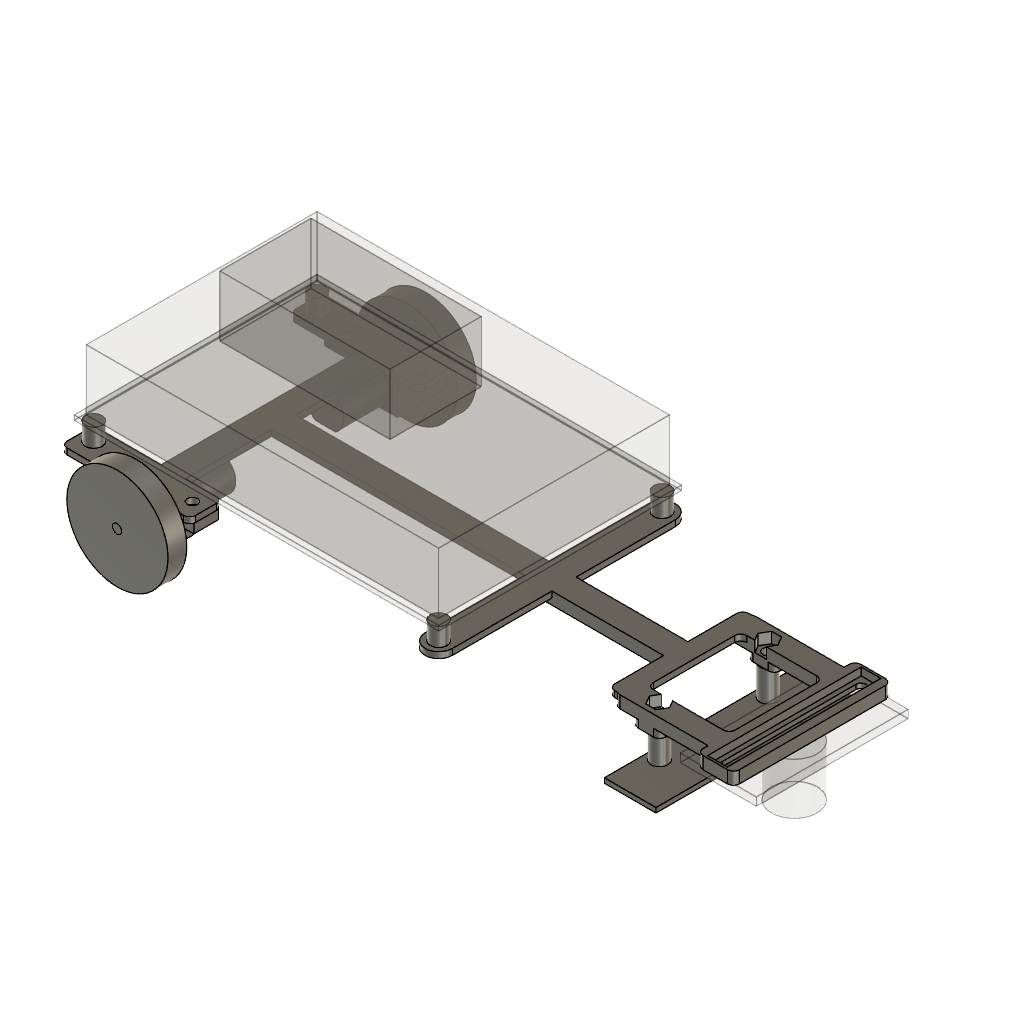
line_follower_chassis_front_caster (Autodesk Fusion 360 design; units mm, degrees)
Autodesk Fusion 360 part; units mm, degrees
ref_plane "WorkPlane1" through (0, 0, 21.65) normal (0, 0, 1) x (1, 0, 0) in component "Frame"
sketch "outline" plane through (0, 0, 21.65) normal (0, 0, 1) x (1, 0, 0) in component "Frame"
  line L0 (-24.25, -43) -> (14.0909, -43)
  line L1 (16.0909, -41) -> (16.0909, -34.25)
  line L2 (14.0909, -32.25) -> (-24.25, -32.25)
  line L3 (-26.25, -34.25) -> (-26.25, -41)
  arc A0 (14.0909, -43) -> (16.0909, -41) centre (14.0909, -41) ccw
  arc A1 (16.0909, -34.25) -> (14.0909, -32.25) centre (14.0909, -34.25) ccw
  arc A2 (-24.25, -32.25) -> (-26.25, -34.25) centre (-24.25, -34.25) ccw
  arc A3 (-26.25, -41) -> (-24.25, -43) centre (-24.25, -41) ccw
  line L4 (137, -22.35) -> (170, -22.35)
  line L5 (172, -20.35) -> (172, -17.4)
  line L6 (170, -15.4) -> (137, -15.4)
  line L7 (135, -17.4) -> (135, -20.35)
  arc A4 (170, -22.35) -> (172, -20.35) centre (170, -20.35) ccw
  arc A5 (172, -17.4) -> (170, -15.4) centre (170, -17.4) ccw
  arc A6 (137, -15.4) -> (135, -17.4) centre (137, -17.4) ccw
  arc A7 (135, -20.35) -> (137, -22.35) centre (137, -20.35) ccw
  line L8 (-24.25, 32.25) -> (14.0909, 32.25)
  line L9 (16.0909, 34.25) -> (16.0909, 41)
  line L10 (14.0909, 43) -> (-24.25, 43)
  line L11 (-26.25, 41) -> (-26.25, 34.25)
  arc A8 (14.0909, 32.25) -> (16.0909, 34.25) centre (14.0909, 34.25) ccw
  arc A9 (16.0909, 41) -> (14.0909, 43) centre (14.0909, 41) ccw
  arc A10 (-24.25, 43) -> (-26.25, 41) centre (-24.25, 41) ccw
  arc A11 (-26.25, 34.25) -> (-24.25, 32.25) centre (-24.25, 34.25) ccw
  line L12 (137, 15.4) -> (170, 15.4)
  line L13 (172, 17.4) -> (172, 20.35)
  line L14 (170, 22.35) -> (137, 22.35)
  line L15 (135, 20.35) -> (135, 17.4)
  arc A12 (170, 15.4) -> (172, 17.4) centre (170, 17.4) ccw
  arc A13 (172, 20.35) -> (170, 22.35) centre (170, 20.35) ccw
  arc A14 (137, 22.35) -> (135, 20.35) centre (137, 20.35) ccw
  arc A15 (135, 17.4) -> (137, 15.4) centre (137, 17.4) ccw
  line L16 (-2, -34) -> (2, -34)
  line L17 (4, -32) -> (4, 32)
  line L18 (2, 34) -> (-2, 34)
  line L19 (-4, 32) -> (-4, -32)
  arc A16 (2, -34) -> (4, -32) centre (2, -32) ccw
  arc A17 (4, 32) -> (2, 34) centre (2, 32) ccw
  arc A18 (-2, 34) -> (-4, 32) centre (-2, 32) ccw
  arc A19 (-4, -32) -> (-2, -34) centre (-2, -32) ccw
  line L20 (2, -4) -> (135, -4)
  line L21 (137, -2) -> (137, 2)
  line L22 (135, 4) -> (2, 4)
  line L23 (0, 2) -> (0, -2)
  arc A20 (135, -4) -> (137, -2) centre (135, -2) ccw
  arc A21 (137, 2) -> (135, 4) centre (135, 2) ccw
  arc A22 (2, 4) -> (0, 2) centre (2, 2) ccw
  arc A23 (0, -2) -> (2, -4) centre (2, -2) ccw
  line L24 (87.25, -36.75) -> (96.25, -36.75)
  line L25 (96.25, -36.75) -> (96.25, 36.75)
  line L26 (96.25, 36.75) -> (87.25, 36.75)
  line L27 (87.25, 36.75) -> (87.25, -36.75)
  circle A24 centre (91.75, -36.75) radius 4.5
  circle A25 centre (91.75, 36.75) radius 4.5
  line L28 (168, -26) -> (176, -26)
  line L29 (178, -24) -> (178, 24)
  line L30 (176, 26) -> (168, 26)
  line L31 (166, 24) -> (166, -24)
  arc A26 (176, -26) -> (178, -24) centre (176, -24) ccw
  arc A27 (178, 24) -> (176, 26) centre (176, 24) ccw
  arc A28 (168, 26) -> (166, 24) centre (168, 24) ccw
  arc A29 (166, -24) -> (168, -26) centre (168, -24) ccw
  line L32 (135, -22.05) -> (137, -22.05)
  line L33 (139, -20.05) -> (139, 20.05)
  line L34 (137, 22.05) -> (135, 22.05)
  line L35 (133, 20.05) -> (133, -20.05)
  arc A30 (137, -22.05) -> (139, -20.05) centre (137, -20.05) ccw
  arc A31 (139, 20.05) -> (137, 22.05) centre (137, 20.05) ccw
  arc A32 (135, 22.05) -> (133, 20.05) centre (135, 20.05) ccw
  arc A33 (133, -20.05) -> (135, -22.05) centre (135, -20.05) ccw
extrude "Extrude1" add sketch "outline" along normal blind 2 makes body 1 in component "Frame"
ref_plane "WorkPlane2" through (0, 0, 20.65) normal (0, 0, 1) x (1, 0, 0) in component "Frame"
sketch "header window" plane through (0, 0, 20.65) normal (0, 0, 1) x (1, 0, 0) in component "Frame"
  line L0 (141, -15.4) -> (164, -15.4)
  line L1 (166, -13.4) -> (166, 13.4)
  line L2 (164, 15.4) -> (141, 15.4)
  line L3 (139, 13.4) -> (139, -13.4)
  arc A0 (164, -15.4) -> (166, -13.4) centre (164, -13.4) ccw
  arc A1 (166, 13.4) -> (164, 15.4) centre (164, 13.4) ccw
  arc A2 (141, 15.4) -> (139, 13.4) centre (141, 13.4) ccw
  arc A3 (139, -13.4) -> (141, -15.4) centre (141, -13.4) ccw
extrude "Extrude2" cut sketch "header window" along normal blind 4 bodies 1 in component "Frame"
ref_plane "WorkPlane3" through (0, 0, 11.65) normal (0, 0, 1) x (1, 0, 0) in component "Frame"
sketch "lip" plane through (0, 0, 11.65) normal (0, 0, 1) x (1, 0, 0) in component "Frame"
  line L0 (-7.4, -41.8) -> (7.4, -41.8)
  line L1 (7.4, -41.8) -> (7.4, -43)
  line L2 (7.4, -43) -> (-7.4, -43)
  line L3 (-7.4, -43) -> (-7.4, -41.8)
extrude "Extrude3" add sketch "lip" along normal blind 10 bodies 1 in component "Frame"
ref_plane "WorkPlane4" through (0, 0, 11.65) normal (0, 0, 1) x (1, 0, 0) in component "Frame"
sketch "lip (1)" plane through (0, 0, 11.65) normal (0, 0, 1) x (1, 0, 0) in component "Frame"
  line L0 (-7.4, 41.8) -> (7.4, 41.8)
  line L1 (7.4, 41.8) -> (7.4, 43)
  line L2 (7.4, 43) -> (-7.4, 43)
  line L3 (-7.4, 43) -> (-7.4, 41.8)
extrude "Extrude4" add sketch "lip (1)" along normal blind 10 bodies 1 in component "Frame"
ref_plane "WorkPlane5" through (0, 0, 19.6) normal (0, 0, 1) x (1, 0, 0) in component "Frame"
sketch "caster pad" plane through (0, 0, 19.6) normal (0, 0, 1) x (1, 0, 0) in component "Frame"
  line L0 (168, -26) -> (176, -26)
  line L1 (178, -24) -> (178, 24)
  line L2 (176, 26) -> (168, 26)
  line L3 (166, 24) -> (166, -24)
  arc A0 (176, -26) -> (178, -24) centre (176, -24) ccw
  arc A1 (178, 24) -> (176, 26) centre (176, 24) ccw
  arc A2 (168, 26) -> (166, 24) centre (168, 24) ccw
  arc A3 (166, -24) -> (168, -26) centre (168, -24) ccw
extrude "Extrude5" add sketch "caster pad" along normal blind 2.05 bodies 1 in component "Frame"
ref_plane "WorkPlane6" through (0, 0, 19.6) normal (0, 0, 1) x (1, 0, 0) in component "Frame"
sketch "keel" plane through (0, 0, 19.6) normal (0, 0, 1) x (1, 0, 0) in component "Frame"
  line L0 (93.75, -4) -> (133, -4)
  line L1 (135, -2) -> (135, 2)
  line L2 (133, 4) -> (93.75, 4)
  line L3 (91.75, 2) -> (91.75, -2)
  arc A0 (133, -4) -> (135, -2) centre (133, -2) ccw
  arc A1 (135, 2) -> (133, 4) centre (133, 2) ccw
  arc A2 (93.75, 4) -> (91.75, 2) centre (93.75, 2) ccw
  arc A3 (91.75, -2) -> (93.75, -4) centre (93.75, -2) ccw
extrude "Extrude6" add sketch "keel" along normal blind 2.05 bodies 1 in component "Frame"
ref_plane "WorkPlane7" through (0, 0, 19.6) normal (0, 0, 1) x (1, 0, 0) in component "Frame"
sketch "finger rib" plane through (0, 0, 19.6) normal (0, 0, 1) x (1, 0, 0) in component "Frame"
  line L0 (137, -22.35) -> (170, -22.35)
  line L1 (172, -20.35) -> (172, -17.4)
  line L2 (170, -15.4) -> (137, -15.4)
  line L3 (135, -17.4) -> (135, -20.35)
  arc A0 (170, -22.35) -> (172, -20.35) centre (170, -20.35) ccw
  arc A1 (172, -17.4) -> (170, -15.4) centre (170, -17.4) ccw
  arc A2 (137, -15.4) -> (135, -17.4) centre (137, -17.4) ccw
  arc A3 (135, -20.35) -> (137, -22.35) centre (137, -20.35) ccw
extrude "Extrude7" add sketch "finger rib" along normal blind 2.05 bodies 1 in component "Frame"
ref_plane "WorkPlane8" through (0, 0, 19.6) normal (0, 0, 1) x (1, 0, 0) in component "Frame"
sketch "finger rib (1)" plane through (0, 0, 19.6) normal (0, 0, 1) x (1, 0, 0) in component "Frame"
  line L0 (137, 15.4) -> (170, 15.4)
  line L1 (172, 17.4) -> (172, 20.35)
  line L2 (170, 22.35) -> (137, 22.35)
  line L3 (135, 20.35) -> (135, 17.4)
  arc A0 (170, 15.4) -> (172, 17.4) centre (170, 17.4) ccw
  arc A1 (172, 20.35) -> (170, 22.35) centre (170, 20.35) ccw
  arc A2 (137, 22.35) -> (135, 20.35) centre (137, 20.35) ccw
  arc A3 (135, 17.4) -> (137, 15.4) centre (137, 17.4) ccw
extrude "Extrude8" add sketch "finger rib (1)" along normal blind 2.05 bodies 1 in component "Frame"
ref_plane "WorkPlane9" through (0, 0, 17.1) normal (0, 0, 1) x (1, 0, 0) in component "Frame"
sketch "IR pad" plane through (0, 0, 17.1) normal (0, 0, 1) x (1, 0, 0) in component "Frame"
  line L0 (143, -22.35) -> (148, -22.35)
  line L1 (150, -20.35) -> (150, -17.4)
  line L2 (148, -15.4) -> (143, -15.4)
  line L3 (141, -17.4) -> (141, -20.35)
  arc A0 (148, -22.35) -> (150, -20.35) centre (148, -20.35) ccw
  arc A1 (150, -17.4) -> (148, -15.4) centre (148, -17.4) ccw
  arc A2 (143, -15.4) -> (141, -17.4) centre (143, -17.4) ccw
  arc A3 (141, -20.35) -> (143, -22.35) centre (143, -20.35) ccw
extrude "Extrude9" add sketch "IR pad" along normal blind 4.55 bodies 1 in component "Frame"
ref_plane "WorkPlane10" through (0, 0, 17.1) normal (0, 0, 1) x (1, 0, 0) in component "Frame"
sketch "IR pad (1)" plane through (0, 0, 17.1) normal (0, 0, 1) x (1, 0, 0) in component "Frame"
  line L0 (143, 15.4) -> (148, 15.4)
  line L1 (150, 17.4) -> (150, 20.35)
  line L2 (148, 22.35) -> (143, 22.35)
  line L3 (141, 20.35) -> (141, 17.4)
  arc A0 (148, 15.4) -> (150, 17.4) centre (148, 17.4) ccw
  arc A1 (150, 20.35) -> (148, 22.35) centre (148, 20.35) ccw
  arc A2 (143, 22.35) -> (141, 20.35) centre (143, 20.35) ccw
  arc A3 (141, 17.4) -> (143, 15.4) centre (143, 17.4) ccw
extrude "Extrude10" add sketch "IR pad (1)" along normal blind 4.55 bodies 1 in component "Frame"
ref_plane "WorkPlane11" through (0, 0, 20.65) normal (0, 0, 1) x (1, 0, 0) in component "Frame"
sketch "screw holes" plane through (0, 0, 20.65) normal (0, 0, 1) x (1, 0, 0) in component "Frame"
  circle A0 centre (-21.75, -36.75) radius 1.7
  circle A1 centre (-21.75, 36.75) radius 1.7
  circle A2 centre (91.75, -36.75) radius 1.7
  circle A3 centre (91.75, 36.75) radius 1.7
  circle A4 centre (-11.6, -37.6) radius 1.7
  circle A5 centre (-11.6, 37.6) radius 1.7
  circle A6 centre (11.6, -37.6) radius 1.7
  circle A7 centre (11.6, 37.6) radius 1.7
extrude "Extrude11" cut sketch "screw holes" along normal blind 4 bodies 1 in component "Frame"
ref_plane "WorkPlane12" through (0, -42.4, 0) normal (0, 1, 0) x (0, 0, 1) in component "Frame"
sketch "shaft slot" plane through (0, -42.4, 0) normal (0, 1, 0) x (1, 0, 0) in component "Frame"
  line L0 (-2.5, -10.65) -> (2.5, -10.65)
  line L1 (2.5, -10.65) -> (2.5, -16.65)
  line L2 (2.5, -16.65) -> (-2.5, -16.65)
  line L3 (-2.5, -16.65) -> (-2.5, -10.65)
  circle A0 centre (0, -16.65) radius 2.5
extrude "Extrude12" cut sketch "shaft slot" along normal mid plane 3.2 bodies 1 in component "Frame"
ref_plane "WorkPlane13" through (0, 42.4, 0) normal (0, 1, 0) x (0, 0, 1) in component "Frame"
sketch "shaft slot (1)" plane through (0, 42.4, 0) normal (0, 1, 0) x (1, 0, 0) in component "Frame"
  line L0 (-2.5, -10.65) -> (2.5, -10.65)
  line L1 (2.5, -10.65) -> (2.5, -16.65)
  line L2 (2.5, -16.65) -> (-2.5, -16.65)
  line L3 (-2.5, -16.65) -> (-2.5, -10.65)
  circle A0 centre (0, -16.65) radius 2.5
extrude "Extrude13" cut sketch "shaft slot (1)" along normal mid plane 3.2 bodies 1 in component "Frame"
ref_plane "WorkPlane14" through (0, 0, 16.1) normal (0, 0, 1) x (1, 0, 0) in component "Frame"
sketch "IR holes" plane through (0, 0, 16.1) normal (0, 0, 1) x (1, 0, 0) in component "Frame"
  circle A0 centre (145.5, -17.85) radius 1.7
  circle A1 centre (145.5, 17.85) radius 1.7
extrude "Extrude14" cut sketch "IR holes" along normal blind 8.55 bodies 1 in component "Frame"
ref_plane "WorkPlane15" through (0, 0, 20.1) normal (0, 0, 1) x (1, 0, 0) in component "Frame"
sketch "IR nut pockets" plane through (0, 0, 20.1) normal (0, 0, 1) x (1, 0, 0) in component "Frame"
  line L0 (148.7909, -17.85) -> (147.1454, -15)
  line L1 (147.1454, -15) -> (143.8546, -15)
  line L2 (143.8546, -15) -> (142.2091, -17.85)
  line L3 (142.2091, -17.85) -> (143.8546, -20.7)
  line L4 (143.8546, -20.7) -> (147.1454, -20.7)
  line L5 (147.1454, -20.7) -> (148.7909, -17.85)
  line L6 (148.7909, 17.85) -> (147.1454, 20.7)
  line L7 (147.1454, 20.7) -> (143.8546, 20.7)
  line L8 (143.8546, 20.7) -> (142.2091, 17.85)
  line L9 (142.2091, 17.85) -> (143.8546, 15)
  line L10 (143.8546, 15) -> (147.1454, 15)
  line L11 (147.1454, 15) -> (148.7909, 17.85)
extrude "Extrude15" cut sketch "IR nut pockets" along normal blind 4.55 bodies 1 in component "Frame"
ref_plane "WorkPlane16" through (0, 0, 18.6) normal (0, 0, 1) x (1, 0, 0) in component "Frame"
sketch "caster slot" plane through (0, 0, 18.6) normal (0, 0, 1) x (1, 0, 0) in component "Frame"
  line L0 (170.3, -22) -> (173.7, -22)
  line L1 (173.7, -22) -> (173.7, 22)
  line L2 (173.7, 22) -> (170.3, 22)
  line L3 (170.3, 22) -> (170.3, -22)
  circle A0 centre (172, -22) radius 1.7
  circle A1 centre (172, 22) radius 1.7
extrude "Extrude16" cut sketch "caster slot" along normal blind 6.05 bodies 1 in component "Frame"
ref_plane "WorkPlane17" through (0, 0, 21.1) normal (0, 0, 1) x (1, 0, 0) in component "Frame"
sketch "caster head channel" plane through (0, 0, 21.1) normal (0, 0, 1) x (1, 0, 0) in component "Frame"
  line L0 (168.75, -25.25) -> (175.25, -25.25)
  line L1 (175.25, -25.25) -> (175.25, 25.25)
  line L2 (175.25, 25.25) -> (168.75, 25.25)
  line L3 (168.75, 25.25) -> (168.75, -25.25)
extrude "Extrude17" cut sketch "caster head channel" along normal blind 3.55 bodies 1 in component "Frame"
ref_plane "WorkPlane1" through (0, 37.6, 0) normal (0, 1, 0) x (0, 0, 1) in component "Motor strap"
sketch "profile" plane through (0, 37.6, 0) normal (0, 1, 0) x (1, 0, 0) in component "Motor strap"
  line L0 (-16.0909, -21.65) -> (-6.2, -21.65)
  line L1 (-6.2, -21.65) -> (-6.2, -11.75)
  line L2 (-6.2, -11.75) -> (6.2, -11.75)
  line L3 (6.2, -11.75) -> (6.2, -21.65)
  line L4 (6.2, -21.65) -> (16.0909, -21.65)
  line L5 (16.0909, -21.65) -> (16.0909, -18.65)
  line L6 (16.0909, -18.65) -> (7.8, -18.65)
  line L7 (7.8, -18.65) -> (7.8, -10.15)
  line L8 (7.8, -10.15) -> (-7.8, -10.15)
  line L9 (-7.8, -10.15) -> (-7.8, -18.65)
  line L10 (-7.8, -18.65) -> (-16.0909, -18.65)
  line L11 (-16.0909, -18.65) -> (-16.0909, -21.65)
extrude "Extrude1'" add sketch "profile" along normal mid plane 8 separate body makes body 2 in component "Motor strap"
ref_plane "WorkPlane2" through (0, 0, 17.65) normal (0, 0, 1) x (1, 0, 0) in component "Motor strap"
sketch "nut traps" plane through (0, 0, 17.65) normal (0, 0, 1) x (1, 0, 0) in component "Motor strap"
  line L0 (-8.3091, 37.6) -> (-9.9546, 40.45)
  line L1 (-9.9546, 40.45) -> (-13.2454, 40.45)
  line L2 (-13.2454, 40.45) -> (-14.8909, 37.6)
  line L3 (-14.8909, 37.6) -> (-13.2454, 34.75)
  line L4 (-13.2454, 34.75) -> (-9.9546, 34.75)
  line L5 (-9.9546, 34.75) -> (-8.3091, 37.6)
  line L6 (14.8909, 37.6) -> (13.2454, 40.45)
  line L7 (13.2454, 40.45) -> (9.9546, 40.45)
  line L8 (9.9546, 40.45) -> (8.3091, 37.6)
  line L9 (8.3091, 37.6) -> (9.9546, 34.75)
  line L10 (9.9546, 34.75) -> (13.2454, 34.75)
  line L11 (13.2454, 34.75) -> (14.8909, 37.6)
extrude "Extrude2'" cut sketch "nut traps" along normal blind 3.4 bodies 2 in component "Motor strap"
ref_plane "WorkPlane3" through (0, 0, 17.65) normal (0, 0, 1) x (1, 0, 0) in component "Motor strap"
sketch "screw holes (2)" plane through (0, 0, 17.65) normal (0, 0, 1) x (1, 0, 0) in component "Motor strap"
  circle A0 centre (-11.6, 37.6) radius 1.7
  circle A1 centre (11.6, 37.6) radius 1.7
extrude "Extrude3'" cut sketch "screw holes (2)" along normal blind 5 bodies 2 in component "Motor strap"
ref_plane "WorkPlane1" through (0, -47.6, 0) normal (0, 1, 0) x (0, 0, 1) in component "Wheels (ref)"
sketch "wheel" plane through (0, -47.6, 0) normal (0, 1, 0) x (1, 0, 0) in component "Wheels (ref)"
  circle A0 centre (0, -16.65) radius 16.65
extrude "Extrude1''" add sketch "wheel" along normal mid plane 6.2 separate body makes body 3 in component "Wheels (ref)"
ref_plane "WorkPlane2" through (0, 47.6, 0) normal (0, 1, 0) x (0, 0, 1) in component "Wheels (ref)"
sketch "wheel (1)" plane through (0, 47.6, 0) normal (0, 1, 0) x (1, 0, 0) in component "Wheels (ref)"
  circle A0 centre (0, -16.65) radius 16.65
extrude "Extrude2''" add sketch "wheel (1)" along normal mid plane 6.2 separate body makes body 4 in component "Wheels (ref)"
ref_plane "WorkPlane1" through (0, 0, 29.65) normal (0, 0, 1) x (1, 0, 0) in component "Perfboard + parts (ref)"
sketch "perfboard" plane through (0, 0, 29.65) normal (0, 0, 1) x (1, 0, 0) in component "Perfboard + parts (ref)"
  line L0 (-25, -40) -> (95, -40)
  line L1 (95, -40) -> (95, 40)
  line L2 (95, 40) -> (-25, 40)
  line L3 (-25, 40) -> (-25, -40)
extrude "Extrude1'''" add sketch "perfboard" along normal blind 1.6 separate body makes body 5 in component "Perfboard + parts (ref)"
ref_plane "WorkPlane2" through (0, 0, 31.25) normal (0, 0, 1) x (1, 0, 0) in component "Perfboard + parts (ref)"
sketch "tallest parts envelope" plane through (0, 0, 31.25) normal (0, 0, 1) x (1, 0, 0) in component "Perfboard + parts (ref)"
  line L0 (-23, -38) -> (93, -38)
  line L1 (93, -38) -> (93, 38)
  line L2 (93, 38) -> (-23, 38)
  line L3 (-23, 38) -> (-23, -38)
extrude "Extrude2'''" add sketch "tallest parts envelope" along normal blind 20 separate body makes body 6 in component "Perfboard + parts (ref)"
ref_plane "WorkPlane1" through (0, 0, 23.65) normal (0, 0, 1) x (1, 0, 0) in component "Brass spacers (ref)"
sketch "board standoffs" plane through (0, 0, 23.65) normal (0, 0, 1) x (1, 0, 0) in component "Brass spacers (ref)"
  circle A0 centre (-21.75, -36.75) radius 2.75
  circle A1 centre (-21.75, 36.75) radius 2.75
  circle A2 centre (91.75, -36.75) radius 2.75
  circle A3 centre (91.75, 36.75) radius 2.75
extrude "Extrude1''''" add sketch "board standoffs" along normal blind 6 separate body makes body 7 at (89.085, -37.4286, 27.65) makes body 8 at (-19.0034, 36.6129, 27.65) makes body 9 at (-19.0034, -36.8871, 27.65) makes body 10 at (89.085, 36.0714, 27.65) in component "Brass spacers (ref)"
ref_plane "WorkPlane2" through (0, 0, 7.1) normal (0, 0, 1) x (1, 0, 0) in component "Brass spacers (ref)"
sketch "IR standoffs" plane through (0, 0, 7.1) normal (0, 0, 1) x (1, 0, 0) in component "Brass spacers (ref)"
  circle A0 centre (145.5, -17.85) radius 2.75
  circle A1 centre (145.5, 17.85) radius 2.75
extrude "Extrude2''''" add sketch "IR standoffs" along normal blind 10 separate body makes body 11 at (145.0225, -20.5582, 10.4333) makes body 12 at (145.8419, 20.5787, 13.7667) in component "Brass spacers (ref)"
ref_plane "WorkPlane1" through (0, 0, 5.5) normal (0, 0, 1) x (1, 0, 0) in component "IR array (ref)"
sketch "pcb" plane through (0, 0, 5.5) normal (0, 0, 1) x (1, 0, 0) in component "IR array (ref)"
  line L0 (141.5, -32) -> (158.5, -32)
  line L1 (158.5, -32) -> (158.5, 32)
  line L2 (158.5, 32) -> (141.5, 32)
  line L3 (141.5, 32) -> (141.5, -32)
extrude "Extrude1'''''" add sketch "pcb" along normal blind 1.6 separate body makes body 13 in component "IR array (ref)"
ref_plane "WorkPlane2" through (0, 0, 3) normal (0, 0, 1) x (1, 0, 0) in component "IR array (ref)"
sketch "eyes" plane through (0, 0, 3) normal (0, 0, 1) x (1, 0, 0) in component "IR array (ref)"
  line L0 (148.5, -29) -> (151.5, -29)
  line L1 (151.5, -29) -> (151.5, 29)
  line L2 (151.5, 29) -> (148.5, 29)
  line L3 (148.5, 29) -> (148.5, -29)
extrude "Extrude2'''''" add sketch "eyes" along normal blind 2.5 separate body makes body 14 in component "IR array (ref)"
ref_plane "WorkPlane1" through (0, 0, 51.25) normal (0, 0, 1) x (1, 0, 0) in component "Battery (ref)"
sketch "battery" plane through (0, 0, 51.25) normal (0, 0, 1) x (1, 0, 0) in component "Battery (ref)"
  line L0 (-2, -15) -> (54, -15)
  line L1 (54, -15) -> (54, 15)
  line L2 (54, 15) -> (-2, 15)
  line L3 (-2, 15) -> (-2, -15)
extrude "Extrude1''''''" add sketch "battery" along normal blind 20 separate body makes body 15 in component "Battery (ref)"
ref_plane "WorkPlane1" through (0, 0, 16.9) normal (0, 0, 1) x (1, 0, 0) in component "Ball caster (ref)"
sketch "plate" plane through (0, 0, 16.9) normal (0, 0, 1) x (1, 0, 0) in component "Ball caster (ref)"
  line L0 (159.5, -25) -> (184.5, -25)
  line L1 (184.5, -25) -> (184.5, 25)
  line L2 (184.5, 25) -> (159.5, 25)
  line L3 (159.5, 25) -> (159.5, -25)
extrude "Extrude1'''''''" add sketch "plate" along normal blind 2.7 separate body makes body 16 in component "Ball caster (ref)"
ref_plane "WorkPlane2" through (0, 0, 0) normal (0, 0, 1) x (1, 0, 0) in component "Ball caster (ref)"
sketch "ball housing" plane through (0, 0, 0) normal (0, 0, 1) x (1, 0, 0) in component "Ball caster (ref)"
  circle A0 centre (172, 0) radius 7.5
extrude "Extrude2''''''" add sketch "ball housing" along normal blind 16.9 separate body makes body 17 in component "Ball caster (ref)"
ref_plane "WorkPlane1" through (0, 0, 11.65) normal (0, 0, 1) x (1, 0, 0) in component "N20 motors (ref)"
sketch "gearbox" plane through (0, 0, 11.65) normal (0, 0, 1) x (1, 0, 0) in component "N20 motors (ref)"
  line L0 (-6, -32.8) -> (6, -32.8)
  line L1 (6, -32.8) -> (6, -41.8)
  line L2 (6, -41.8) -> (-6, -41.8)
  line L3 (-6, -41.8) -> (-6, -32.8)
extrude "Extrude1''''''''" add sketch "gearbox" along normal blind 10 separate body makes body 18 in component "N20 motors (ref)"
ref_plane "WorkPlane2" through (0, -25.3, 0) normal (0, 1, 0) x (0, 0, 1) in component "N20 motors (ref)"
sketch "can" plane through (0, -25.3, 0) normal (0, 1, 0) x (1, 0, 0) in component "N20 motors (ref)"
  circle A0 centre (0, -16.65) radius 6
extrude "Extrude2'''''''" add sketch "can" along normal mid plane 15 separate body makes body 19 in component "N20 motors (ref)"
ref_plane "WorkPlane3" through (0, -46.3, 0) normal (0, 1, 0) x (0, 0, 1) in component "N20 motors (ref)"
sketch "shaft" plane through (0, -46.3, 0) normal (0, 1, 0) x (1, 0, 0) in component "N20 motors (ref)"
  circle A0 centre (0, -16.65) radius 1.5
extrude "Extrude3''" add sketch "shaft" along normal mid plane 9 separate body makes body 20 in component "N20 motors (ref)"
ref_plane "WorkPlane4" through (0, 0, 11.65) normal (0, 0, 1) x (1, 0, 0) in component "N20 motors (ref)"
sketch "gearbox (1)" plane through (0, 0, 11.65) normal (0, 0, 1) x (1, 0, 0) in component "N20 motors (ref)"
  line L0 (-6, 32.8) -> (6, 32.8)
  line L1 (6, 32.8) -> (6, 41.8)
  line L2 (6, 41.8) -> (-6, 41.8)
  line L3 (-6, 41.8) -> (-6, 32.8)
extrude "Extrude4'" add sketch "gearbox (1)" along normal blind 10 separate body makes body 21 in component "N20 motors (ref)"
ref_plane "WorkPlane5" through (0, 25.3, 0) normal (0, 1, 0) x (0, 0, 1) in component "N20 motors (ref)"
sketch "can (1)" plane through (0, 25.3, 0) normal (0, 1, 0) x (1, 0, 0) in component "N20 motors (ref)"
  circle A0 centre (0, -16.65) radius 6
extrude "Extrude5'" add sketch "can (1)" along normal mid plane 15 separate body makes body 22 in component "N20 motors (ref)"
ref_plane "WorkPlane6" through (0, 46.3, 0) normal (0, 1, 0) x (0, 0, 1) in component "N20 motors (ref)"
sketch "shaft (1)" plane through (0, 46.3, 0) normal (0, 1, 0) x (1, 0, 0) in component "N20 motors (ref)"
  circle A0 centre (0, -16.65) radius 1.5
extrude "Extrude6'" add sketch "shaft (1)" along normal mid plane 9 separate body makes body 23 in component "N20 motors (ref)"
ref_plane "WorkPlane7" through (0, 0, 4.65) normal (0, 0, 1) x (1, 0, 0) in component "N20 motors (ref)"
sketch "can flats" plane through (0, 0, 4.65) normal (0, 0, 1) x (1, 0, 0) in component "N20 motors (ref)"
  line L0 (-12, -43) -> (12, -43)
  line L1 (12, -43) -> (12, 43)
  line L2 (12, 43) -> (-12, 43)
  line L3 (-12, 43) -> (-12, -43)
extrude "Extrude7'" cut sketch "can flats" along normal blind 7 bodies 18 19 20 21 22 23 in component "N20 motors (ref)"
ref_plane "WorkPlane8" through (0, 0, 21.65) normal (0, 0, 1) x (1, 0, 0) in component "N20 motors (ref)"
sketch "can flats (1)" plane through (0, 0, 21.65) normal (0, 0, 1) x (1, 0, 0) in component "N20 motors (ref)"
  line L0 (-12, -43) -> (12, -43)
  line L1 (12, -43) -> (12, 43)
  line L2 (12, 43) -> (-12, 43)
  line L3 (-12, 43) -> (-12, -43)
extrude "Extrude8'" cut sketch "can flats (1)" along normal blind 7 bodies 18 19 20 21 22 23 in component "N20 motors (ref)"
component "Frame" placed x (1, 0, 0) y (0, 1, 0) z (0, 0, 1) at (0, 0, 0)
component "Motor strap" placed x (1, 0, 0) y (0, 1, 0) z (0, 0, 1) at (0, 0, 0)
component "Motor strap" placed x (1, 0, 0) y (0, 1, 0) z (0, 0, 1) at (0, -75.2, 0)
component "Wheels (ref)" placed x (1, 0, 0) y (0, 1, 0) z (0, 0, 1) at (0, 0, 0)
component "Perfboard + parts (ref)" placed x (1, 0, 0) y (0, 1, 0) z (0, 0, 1) at (0, 0, 0)
component "Brass spacers (ref)" placed x (1, 0, 0) y (0, 1, 0) z (0, 0, 1) at (0, 0, 0)
component "IR array (ref)" placed x (1, 0, 0) y (0, 1, 0) z (0, 0, 1) at (0, 0, 0)
component "Battery (ref)" placed x (1, 0, 0) y (0, 1, 0) z (0, 0, 1) at (0, 0, 0)
component "Ball caster (ref)" placed x (1, 0, 0) y (0, 1, 0) z (0, 0, 1) at (0, 0, 0)
component "N20 motors (ref)" placed x (1, 0, 0) y (0, 1, 0) z (0, 0, 1) at (0, 0, 0)
